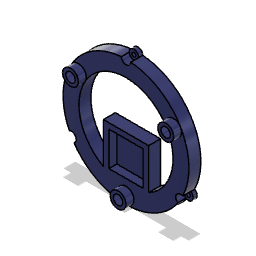
BASEPLATE v4 v5 (Autodesk Fusion 360 design; units mm, degrees)
Autodesk Fusion 360 part; units mm, degrees
sketch "Sketch1" plane through (0, 0, 0) normal (0, 0, 1) x (1, 0, 0)
  line L0 (-60, 34.641) -> (60, 34.641) construction
  line L1 (-60, 34.641) -> (0, -69.282) construction
  line L2 (60, 34.641) -> (0, -69.282) construction
  line L3 (0, -69.282) -> (0, 34.641) construction
  line L4 (-60, 34.641) -> (30, -17.3205) construction
  circle A0 centre (60, 34.641) radius 6
  circle A1 centre (60, 34.641) radius 10
  circle A2 centre (-60, 34.641) radius 10
  circle A3 centre (-60, 34.641) radius 6
  circle A4 centre (0, -69.282) radius 10
  circle A5 centre (0, -69.282) radius 6
  circle A6 centre (0, 0) radius 79.282
  circle A7 centre (0, 0) radius 59.282
  circle A8 centre (0, 79.282) radius 2.5
  circle A9 centre (0, 79.282) radius 6
  circle A10 centre (-68.6603, -39.641) radius 2.5
  circle A11 centre (-68.6603, -39.641) radius 6
  circle A12 centre (68.6603, -39.641) radius 2.5
  circle A13 centre (68.6603, -39.641) radius 6
  line L5 (21.5, -50.782) -> (-21.5, -50.782)
  line L6 (-21.5, -50.782) -> (-21.5, -7.782)
  line L7 (-21.5, -7.782) -> (21.5, -7.782)
  line L8 (21.5, -7.782) -> (21.5, -50.782)
  line L9 (21.5, -50.782) -> (-21.5, -7.782) construction
  line L10 (-21.5, -50.782) -> (21.5, -7.782) construction
  line L11 (-28.5, -0.782) -> (28.5, -0.782)
  line L12 (28.5, -0.782) -> (28.5, -57.782)
  line L13 (28.5, -57.782) -> (-28.5, -57.782)
  line L14 (-28.5, -57.782) -> (-28.5, -0.782)
  point P0 (0, -29.282)
  dimension "d47_1" = 12
  dimension "d48_1" = 20
  dimension "d50_1" = 360
  dimension "d55_1" = 5
  dimension "d56_1" = 12
  dimension "d58_1" = 360
  dimension "d65_1" = 43
  dimension "d66_1" = 43
  dimension "d68_1" = -7
  dimension "d69_1" = 40
  constraint horizontal L0
  constraint midpoint L0 L3.end
  constraint perpendicular L0 L3
  constraint midpoint L2 L4.end
  constraint perpendicular L2 L4
  constraint coincident L4 A6.centre
  constraint coincident L3 A6.centre
  constraint coincident L0.end L2.start
  constraint coincident A6.centre A7.centre
  constraint tangent A4 A6
  constraint tangent A4 A7
  constraint coincident A6 A8.centre
  constraint concentric A8 A9
  constraint horizontal L5
  constraint perpendicular L5 L6
  constraint parallel L5 L7
  constraint parallel L6 L8
  constraint coincident L9 P0
  constraint coincident L10 P0
  constraint coincident L3 P0
  measures "d47_1" diameter of A0
  measures "d48_1" diameter of A1
  measures "d55_1" diameter of A8
  measures "d56_1" diameter of A9
  measures "d65_1" distance of L6.end L7.end
  measures "d66_1" distance of L5.end L6.end
  measures "d69_1" distance of L1.end P0
extrude "Extrude5" add sketch "Sketch1" along normal blind 15 contours A1 | A1 A4 A6 A7 A13 L12 L13 | A1 A2 A6 A7 A9 | A2 A4 A6 A7 A11 L13 L14 | A2 | A7 L12 L13 | A7 L11 L12 L13 L14 | A7 L13 L14 | A7 L13 | A4
extrude "Extrude6" add sketch "Sketch1" along normal blind 5 contours A6 A8 A9 | A6 A8 A9 | A6 A12 A13 | A6 A12 A13 | A6 A10 A11 | A6 A10 A11 | L5 L6 L7 L8
extrude "Extrude7" add sketch "Sketch1" along normal blind 25 contours A1 | A2 | A4
